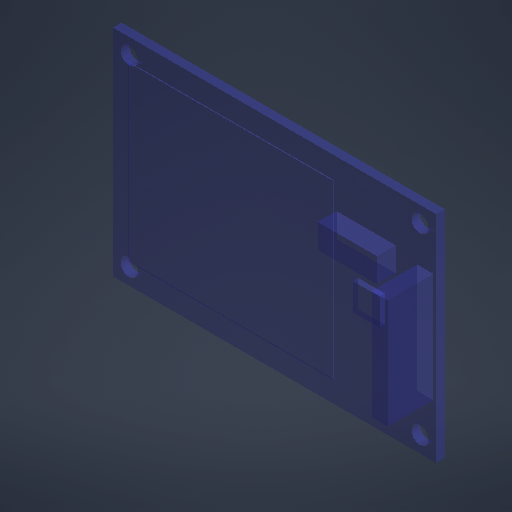
# Autodesk Inventor part: MFRC522_RFID_Module
Saved by Autodesk Inventor 2027.1 (Build 311270010, 270A)
## iProperties
Part Number: MFRC522_RFID_Module
Material: Generic
Document SubType Name: Modeling
Designer: austin
Appearance: Blue
Author: austin
Autodesk Inventor part; units mm, degrees
ref_plane "YZ Plane" through (0, 0, 0) normal (1, 0, 0) x (0, 1, 0)
ref_plane "XZ Plane" through (0, 0, 0) normal (0, 1, 0) x (-1, 0, 0)
sketch "Sketch1" plane through (0, 0, 0) normal (0, 0, 1) x (1, 0, 0)
  line L0 (-30, -20) -> (30, -20)
  line L1 (30, -20) -> (30, 20)
  line L2 (30, 20) -> (-30, 20)
  line L3 (-30, 20) -> (-30, -20)
  constraints: 8 end point, 2 parallel, 1 horizontal, 1 perpendicular
extrude "Extrusion1" add sketch "Sketch1" along normal blind 1.6
sketch "Sketch2" plane through (0, 0, 0) normal (0, 0, 1) x (1, 0, 0)
  circle A0 centre (-27, -17) radius 1.6
  circle A1 centre (27, -17) radius 1.6
  circle A2 centre (-27, 17) radius 1.6
  circle A3 centre (27, 17) radius 1.6
  constraints: 4 centre point
extrude "Extrusion2" cut sketch "Sketch2" along normal blind 2
ref_plane "Work Plane1" through (0, 0, 1.6) normal (0, 0, 1) x (1, 0, 0)
sketch "Sketch3" plane through (0, 0, 1.6) normal (0, 0, 1) x (1, 0, 0)
  line L0 (-27, -16) -> (11, -16)
  line L1 (11, -16) -> (11, 16)
  line L2 (11, 16) -> (-27, 16)
  line L3 (-27, 16) -> (-27, -16)
  constraints: 8 end point, 2 parallel, 1 horizontal, 1 perpendicular
extrude "Extrusion3" add sketch "Sketch3" along normal blind 0.2
sketch "Sketch4" plane through (0, 0, 1.6) normal (0, 0, 1) x (1, 0, 0)
  line L0 (15.5, -2.5) -> (20.5, -2.5)
  line L1 (20.5, -2.5) -> (20.5, 2.5)
  line L2 (20.5, 2.5) -> (15.5, 2.5)
  line L3 (15.5, 2.5) -> (15.5, -2.5)
  constraints: 8 end point, 2 parallel, 1 horizontal, 1 perpendicular
extrude "Extrusion4" add sketch "Sketch4" along normal blind 1
sketch "Sketch5" plane through (0, 0, 1.6) normal (0, 0, 1) x (1, 0, 0)
  line L0 (11.5, 6.75) -> (22.5, 6.75)
  line L1 (22.5, 6.75) -> (22.5, 11.25)
  line L2 (22.5, 11.25) -> (11.5, 11.25)
  line L3 (11.5, 11.25) -> (11.5, 6.75)
  constraints: 8 end point, 2 parallel, 1 horizontal, 1 perpendicular
extrude "Extrusion5" add sketch "Sketch5" along normal blind 3.5
sketch "Sketch6" plane through (0, 0, 1.6) normal (0, 0, 1) x (1, 0, 0)
  line L0 (26.5, -10.15) -> (29.5, -10.15)
  line L1 (29.5, -10.15) -> (29.5, 10.15)
  line L2 (29.5, 10.15) -> (26.5, 10.15)
  line L3 (26.5, 10.15) -> (26.5, -10.15)
  constraints: 8 end point, 2 parallel, 1 horizontal, 1 perpendicular
extrude "Extrusion6" add sketch "Sketch6" along normal blind 8.5
body "Solid1"
